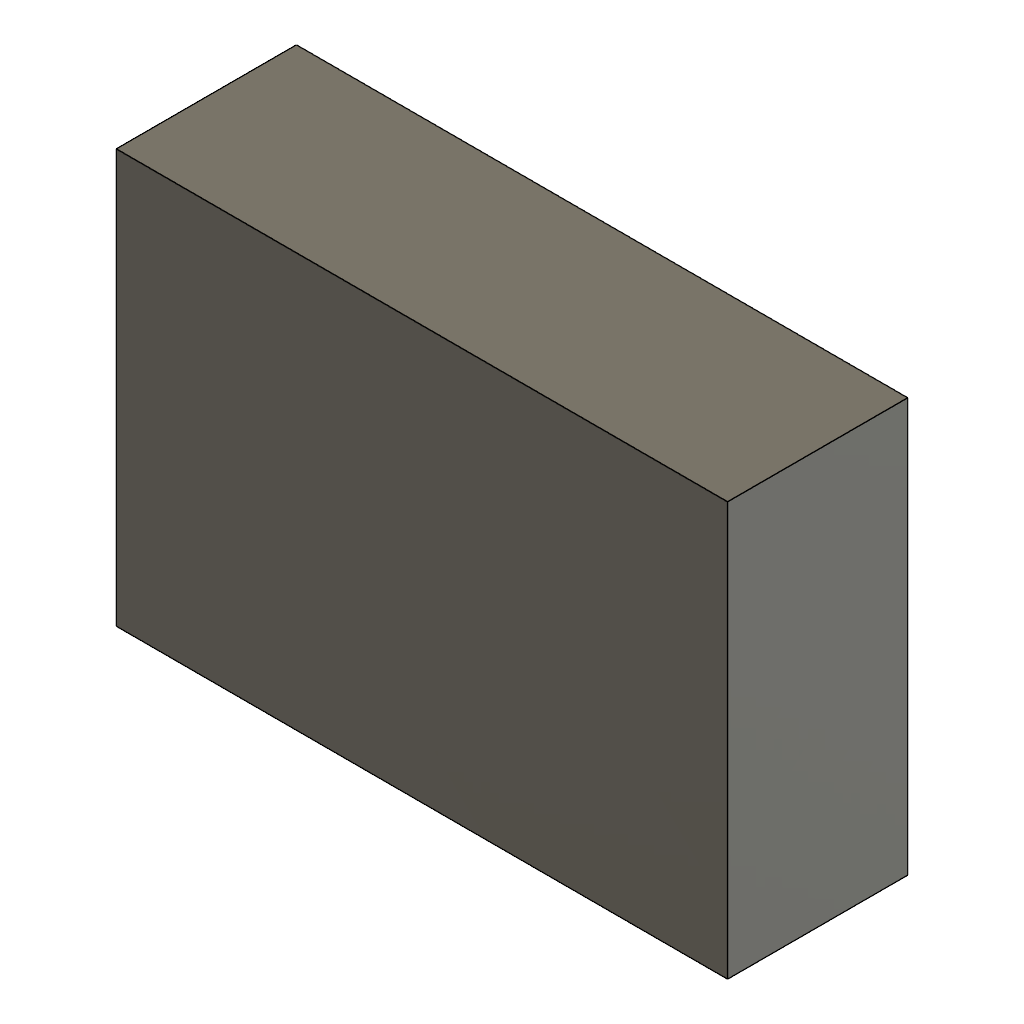
control-before (Autodesk Fusion 360 design; units mm, degrees)
part number: 2026-11-23-13-21-12-897
Autodesk Fusion 360 part; units mm, degrees
sketch "Sketch1" plane through (0, 0, 0) normal (0, 0, 1) x (1, 0, 0)
  line L0 (0, 0) -> (17.3, 0)
  line L1 (17.3, 0) -> (17.3, 11.7)
  line L2 (17.3, 11.7) -> (0, 11.7)
  line L3 (0, 11.7) -> (0, 0)
extrude "ControlledBoss" add sketch "Sketch1" along normal blind 5.1
